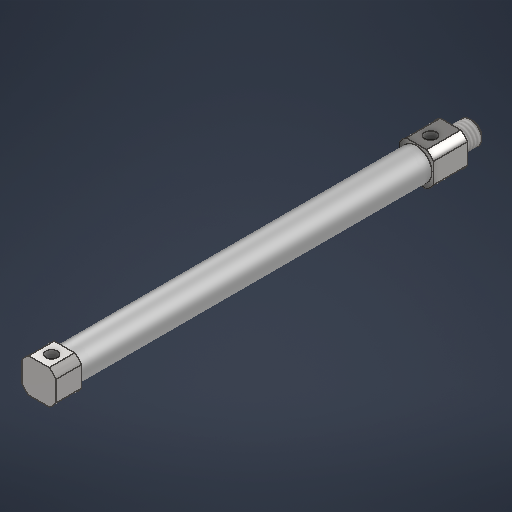
# Autodesk Inventor part: CDJ2B10_Body
Saved by Autodesk Inventor 2026.2 (Build 302298010, 298A)
## iProperties
Created: 2026-05-07
Part Number: CDJ2B10_Body
Material: 스테인리스스틸
Document SubType Name: Modeling
Designer: work
Density: 8 g/cm^3
Appearance: 반연마
Author: work
Autodesk Inventor part; units mm, degrees
ref_plane "YZ Plane" through (0, 0, 0) normal (1, 0, 0) x (0, 1, 0)
ref_plane "XZ Plane" through (0, 0, 0) normal (0, 1, 0) x (-1, 0, 0)
ref_plane "XY Plane" through (0, 0, 0) normal (0, 0, 1) x (1, 0, 0)
sketch "스케치1" plane through (0, 0, 0) normal (0, 0, 1) x (1, 0, 0)
  circle A0 centre (0, 0) radius 5.5
  dimension "d0" = 11
  constraints: 1 centre point, 1 coincident
  measures "d0" diameter of A0
extrude "돌출1" add sketch "스케치1" along normal blind 124
sketch "스케치2" plane through (0, 0, 124) normal (0, 0, 1) x (1, 0, 0)
  circle A0 centre (0, 0) radius 7
  line L0 (-6, -6) -> (6, -6)
  line L1 (6, -6) -> (6, 6)
  line L2 (6, 6) -> (-6, 6)
  line L3 (-6, 6) -> (-6, -6)
  line L4 (-6, -6) -> (6, 6) construction
  line L5 (6, -6) -> (-6, 6) construction
  point P0 (-6, 3.6056)
  point P1 (-6, -3.6056)
  point P2 (-3.6056, -6)
  point P3 (3.6056, -6)
  point P4 (6, -3.6056)
  point P5 (6, 3.6056)
  point P6 (3.6056, 6)
  point P7 (-3.6056, 6)
  dimension "d3" = 14
  dimension "d4" = 12
  dimension "d5" = 12
  constraints: 12 end point, 2 midpoint, 2 parallel, 1 centre point, 1 coincident, 1 horizontal, 1 perpendicular
  measures "d3" diameter of A0
  measures "d4" distance between parallel lines of L0 L2
  measures "d5" distance of L0.start L0.end
extrude "돌출2" add sketch "스케치2" along normal blind 9 contours L1 A0 L0 L3 L2
sketch "스케치3" plane through (0, 0, 0) normal (0, 0, -1) x (-1, 0, 0)
  line L0 (-6, 6) -> (6, 6)
  line L1 (6, 6) -> (6, -6)
  line L2 (6, -6) -> (-6, -6)
  line L3 (-6, -6) -> (-6, 6)
  line L4 (-6, 6) -> (6, -6) construction
  line L5 (6, 6) -> (-6, -6) construction
  line L6 (6, 3.6056) -> (6, -3.6056) projected
  circle A0 centre (0, 0) radius 7
  point P0 (-6, -3.6056)
  point P1 (-3.6056, -6)
  point P2 (3.6056, -6)
  point P3 (3.6056, 6)
  point P4 (-3.6056, 6)
  point P5 (-6, 3.6056)
  dimension "d8" = 12
  dimension "d9" = 12
  constraints: 12 end point, 2 midpoint, 2 parallel, 1 coincident, 1 horizontal, 1 perpendicular, 3 other
  measures "d8" distance of L1.end L2.end
  measures "d9" distance of L0.end L1.end
extrude "돌출3" add sketch "스케치3" along normal blind 12 contours L0 A0 L1 L2 L3
sketch "스케치4" plane through (0, 0, -12) normal (0, 0, -1) x (-1, 0, 0)
  circle A0 centre (0, 0) radius 4
  dimension "d12" = 8
  constraints: 1 centre point, 1 coincident
  measures "d12" diameter of A0
extrude "돌출4" add sketch "스케치4" along normal blind 8
thread "스레드1" size "M8x1.25" class "6g" standard "ISO Metric profile" full length
chamfer "모따기1" distance 1 angle 45 2 edges at (4, 0, -12) (4, 0, -20)
sketch "스케치5" plane through (-3.6056, 6, 124) normal (0, 1, 0) x (1, 0, 0)
  line L0 (0, 124) -> (7.2111, 124) projected
  line L1 (7.2111, 124) -> (7.2111, 136) projected
  line L2 (0, 136) -> (7.2111, 136) projected
  line L3 (0, 124) -> (0, 136) projected
  line L4 (7.2111, 0) -> (0, 0) projected
  line L5 (0, 0) -> (0, -9) projected
  line L6 (7.2111, -9) -> (0, -9) projected
  line L7 (7.2111, 0) -> (7.2111, -9) projected
  line L8 (0, -4.5) -> (7.2111, -4.5) construction
  line L9 (3.6056, 124) -> (3.6056, 136) construction
  point P0 (3.6056, -4.5)
  point P1 (3.6056, 129)
  dimension "d20" = 5
  constraints: 4 end point, 4 midpoint, 1 point on line
  measures "d20" distance from line of L0 point (3.606, 129)
hole "구멍1" at (0, 6, 128.5) at (0, 6, -5) direction (0, -1, 0) diameter 4.134 depth 5 thread size "M5x0.8" class "6H" standard "ANSI Metric M Profile"
sketch "스케치6" plane through (0, 0, -20) normal (0, 0, -1) x (-1, 0, 0)
  circle A0 centre (0, 0) radius 2
  dimension "d28" = 4
  constraints: 1 centre point, 1 coincident
  measures "d28" diameter of A0
extrude "돌출5" cut sketch "스케치6" against normal blind 142
